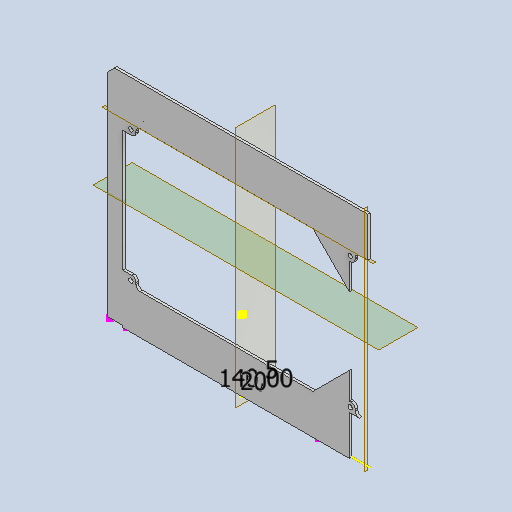
# Autodesk Inventor part: sensor board
Saved by Autodesk Inventor 2025 (Build 290162000, 162)
## iProperties
Created: 2026-07-27
Part Number: sensor board
Material: Типовые
Document SubType Name: Modeling
Designer: garin
Density: 1 g/cm^3
Appearance: По умолчанию
Author: garin
Autodesk Inventor part; units mm, degrees
ref_plane "YZ Plane" through (0, 0, 0) normal (1, 0, 0) x (0, 1, 0)
ref_plane "XZ Plane" through (0, 0, 0) normal (0, 1, 0) x (-1, 0, 0)
ref_plane "XY Plane" through (0, 0, 0) normal (0, 0, 1) x (1, 0, 0)
sketch "Эскиз1" plane through (0, 0, 0) normal (0, 0, 1) x (1, 0, 0)
  line L0 (0, 0) -> (-80.25, 0) construction
  line L1 (-80.25, 0) -> (-80.25, -18.086) construction
  line L2 (-80.25, -18.086) -> (0, -18.086) construction
  line L3 (0, -18.086) -> (0, 0) construction
  line L4 (-80.25, -18.086) -> (-80.25, -42.186) construction
  line L5 (-80.25, -18.086) -> (-56.15, -18.086) construction
  line L6 (-80.25, -42.186) -> (76.75, -42.186)
  line L7 (76.75, -42.186) -> (76.75, 91.214)
  line L8 (76.75, 91.214) -> (-80.25, 91.214)
  line L9 (-80.25, 91.214) -> (-80.25, -42.186)
  line L10 (-80.25, -42.186) -> (76.75, -42.186)
  line L11 (76.75, -42.186) -> (76.75, -18.086)
  line L12 (76.75, -18.086) -> (-60.75, -18.086)
  line L13 (-80.25, -18.086) -> (-80.25, -42.186)
  line L14 (76.75, 91.214) -> (-80.25, 91.214)
  line L15 (-80.25, 91.214) -> (-80.25, 67.114)
  line L16 (-80.25, 67.114) -> (76.75, 67.114)
  line L17 (76.75, 67.114) -> (76.75, 91.214)
  line L18 (-80.25, -42.186) -> (-71.25, -42.186)
  line L19 (-71.25, -42.186) -> (-71.25, 88.814)
  line L20 (-71.25, 88.814) -> (-80.25, 88.814)
  line L21 (-80.25, 88.814) -> (-80.25, -42.186)
  line L22 (76.75, -42.186) -> (65.75, -42.186)
  line L23 (65.75, -42.186) -> (65.75, 88.814)
  line L24 (65.75, 88.814) -> (76.75, 88.814)
  line L25 (76.75, 88.814) -> (76.75, -42.186)
  line L26 (76.75, -42.186) -> (41.75, -42.186)
  line L27 (41.75, -42.186) -> (61.75, -42.186) construction
  line L28 (76.75, 23.314) -> (-80.25, 23.314) construction
  line L29 (65.75, 67.114) -> (65.75, 45.114)
  line L30 (65.75, 45.114) -> (43.75, 67.114)
  line L31 (65.75, 45.114) -> (96.8627, 45.114) construction
  line L32 (-71.25, 23.314) -> (-80.25, 23.314)
  line L33 (-80.25, 23.314) -> (-80.25, 50.814)
  line L34 (-80.25, 50.814) -> (-71.25, 50.814)
  line L35 (-71.25, 50.814) -> (-71.25, 23.314)
  line L36 (0, -18.086) -> (0, 67.114) construction
  line L37 (-80.25, 23.314) -> (76.75, 23.314) construction
  line L38 (76.75, 91.214) -> (76.75, -42.186)
  line L39 (76.75, 24.514) -> (-71.25, 24.514) construction
  line L40 (65.75, 3.914) -> (43.75, -18.086)
  line L41 (60.8932, -21.756) -> (60.8932, -22.256) construction
  line L42 (60.8932, -21.756) -> (61.2932, -21.756) construction
  line L43 (61.2932, -21.756) -> (61.2932, -22.256) construction
  line L44 (61.2932, -22.256) -> (60.8932, -22.256) construction
  line L45 (61.2932, -26.836) -> (61.2932, -27.336) construction
  line L46 (61.2932, -27.336) -> (60.8932, -27.336) construction
  line L47 (60.8932, -26.836) -> (60.8932, -27.336) construction
  line L48 (60.8932, -26.836) -> (61.2932, -26.836) construction
  line L49 (60.8932, -31.916) -> (60.8932, -32.416) construction
  line L50 (60.8932, -31.916) -> (61.2932, -31.916) construction
  line L51 (61.2932, -31.916) -> (61.2932, -32.416) construction
  line L52 (61.2932, -32.416) -> (60.8932, -32.416) construction
  line L53 (-64.3932, -21.756) -> (-64.3932, -22.256) construction
  line L54 (-64.7932, -22.256) -> (-64.3932, -22.256) construction
  line L55 (-64.7932, -21.756) -> (-64.7932, -22.256) construction
  line L56 (-64.3932, -21.756) -> (-64.7932, -21.756) construction
  line L57 (-64.7932, -26.836) -> (-64.7932, -27.336) construction
  line L58 (-64.3932, -26.836) -> (-64.7932, -26.836) construction
  line L59 (-64.3932, -26.836) -> (-64.3932, -27.336) construction
  line L60 (-64.7932, -27.336) -> (-64.3932, -27.336) construction
  line L61 (-64.3932, -31.916) -> (-64.3932, -32.416) construction
  line L62 (-64.7932, -32.416) -> (-64.3932, -32.416) construction
  line L63 (-64.7932, -31.916) -> (-64.7932, -32.416) construction
  line L64 (-64.3932, -31.916) -> (-64.7932, -31.916) construction
  line L65 (-64.3932, 80.944) -> (-64.3932, 81.444) construction
  line L66 (-64.3932, 80.944) -> (-64.7932, 80.944) construction
  line L67 (-64.7932, 80.944) -> (-64.7932, 81.444) construction
  line L68 (-64.7932, 81.444) -> (-64.3932, 81.444) construction
  line L69 (-64.7932, 75.864) -> (-64.7932, 76.364) construction
  line L70 (-64.7932, 76.364) -> (-64.3932, 76.364) construction
  line L71 (-64.3932, 75.864) -> (-64.3932, 76.364) construction
  line L72 (-64.3932, 75.864) -> (-64.7932, 75.864) construction
  line L73 (-64.3932, 70.784) -> (-64.3932, 71.284) construction
  line L74 (-64.3932, 70.784) -> (-64.7932, 70.784) construction
  line L75 (-64.7932, 70.784) -> (-64.7932, 71.284) construction
  line L76 (-64.7932, 71.284) -> (-64.3932, 71.284) construction
  line L77 (60.8932, 80.944) -> (60.8932, 81.444) construction
  line L78 (61.2932, 81.444) -> (60.8932, 81.444) construction
  line L79 (61.2932, 80.944) -> (61.2932, 81.444) construction
  line L80 (60.8932, 80.944) -> (61.2932, 80.944) construction
  line L81 (61.2932, 75.864) -> (61.2932, 76.364) construction
  line L82 (60.8932, 75.864) -> (61.2932, 75.864) construction
  line L83 (60.8932, 75.864) -> (60.8932, 76.364) construction
  line L84 (61.2932, 76.364) -> (60.8932, 76.364) construction
  line L85 (60.8932, 70.784) -> (60.8932, 71.284) construction
  line L86 (61.2932, 71.284) -> (60.8932, 71.284) construction
  line L87 (61.2932, 70.784) -> (61.2932, 71.284) construction
  line L88 (60.8932, 70.784) -> (61.2932, 70.784) construction
  line L89 (-8.01, 84.194) -> (-8.01, 83.754) construction
  line L90 (-8.45, 84.194) -> (-8.01, 84.194) construction
  line L91 (-8.45, 83.754) -> (-8.45, 84.194) construction
  line L92 (-8.01, 83.754) -> (-8.45, 83.754) construction
  line L93 (-5.47, 84.194) -> (-5.47, 83.754) construction
  line L94 (-5.91, 84.194) -> (-5.47, 84.194) construction
  line L95 (-5.91, 83.754) -> (-5.91, 84.194) construction
  line L96 (-5.47, 83.754) -> (-5.91, 83.754) construction
  line L97 (-2.93, 84.194) -> (-2.93, 83.754) construction
  line L98 (-3.37, 84.194) -> (-2.93, 84.194) construction
  line L99 (-3.37, 83.754) -> (-3.37, 84.194) construction
  line L100 (-2.93, 83.754) -> (-3.37, 83.754) construction
  line L101 (-0.39, 84.194) -> (-0.39, 83.754) construction
  line L102 (-0.83, 84.194) -> (-0.39, 84.194) construction
  line L103 (-0.83, 83.754) -> (-0.83, 84.194) construction
  line L104 (-0.39, 83.754) -> (-0.83, 83.754) construction
  line L105 (2.15, 84.194) -> (2.15, 83.754) construction
  line L106 (1.71, 84.194) -> (2.15, 84.194) construction
  line L107 (1.71, 83.754) -> (1.71, 84.194) construction
  line L108 (2.15, 83.754) -> (1.71, 83.754) construction
  line L109 (4.69, 84.194) -> (4.69, 83.754) construction
  line L110 (4.25, 84.194) -> (4.69, 84.194) construction
  line L111 (4.25, 83.754) -> (4.25, 84.194) construction
  line L112 (4.69, 83.754) -> (4.25, 83.754) construction
  line L113 (66.3002, 49.1566) -> (65.9891, 48.8455) construction
  line L114 (65.9891, 49.4678) -> (66.3002, 49.1566) construction
  line L115 (65.6779, 49.1566) -> (65.9891, 49.4678) construction
  line L116 (65.9891, 48.8455) -> (65.6779, 49.1566) construction
  line L117 (64.5041, 50.9527) -> (64.193, 50.6416) construction
  line L118 (64.193, 51.2638) -> (64.5041, 50.9527) construction
  line L119 (63.8819, 50.9527) -> (64.193, 51.2638) construction
  line L120 (64.193, 50.6416) -> (63.8819, 50.9527) construction
  line L121 (62.7081, 52.7487) -> (62.397, 52.4376) construction
  line L122 (62.397, 53.0599) -> (62.7081, 52.7487) construction
  line L123 (62.0858, 52.7487) -> (62.397, 53.0599) construction
  line L124 (62.397, 52.4376) -> (62.0858, 52.7487) construction
  line L125 (60.912, 54.5448) -> (60.6009, 54.2337) construction
  line L126 (60.6009, 54.8559) -> (60.912, 54.5448) construction
  line L127 (60.2898, 54.5448) -> (60.6009, 54.8559) construction
  line L128 (60.6009, 54.2337) -> (60.2898, 54.5448) construction
  line L129 (59.116, 56.3409) -> (58.8048, 56.0297) construction
  line L130 (58.8048, 56.652) -> (59.116, 56.3409) construction
  line L131 (58.4937, 56.3409) -> (58.8048, 56.652) construction
  line L132 (58.8048, 56.0297) -> (58.4937, 56.3409) construction
  line L133 (57.3199, 58.1369) -> (57.0088, 57.8258) construction
  line L134 (57.0088, 58.448) -> (57.3199, 58.1369) construction
  line L135 (56.6977, 58.1369) -> (57.0088, 58.448) construction
  line L136 (57.0088, 57.8258) -> (56.6977, 58.1369) construction
  line L137 (57.3199, -9.1089) -> (57.0088, -8.7978) construction
  line L138 (57.0088, -8.7978) -> (56.6977, -9.1089) construction
  line L139 (56.6977, -9.1089) -> (57.0088, -9.42) construction
  line L140 (57.0088, -9.42) -> (57.3199, -9.1089) construction
  line L141 (59.116, -7.3129) -> (58.8048, -7.0017) construction
  line L142 (58.8048, -7.0017) -> (58.4937, -7.3129) construction
  line L143 (58.4937, -7.3129) -> (58.8048, -7.624) construction
  line L144 (58.8048, -7.624) -> (59.116, -7.3129) construction
  line L145 (60.912, -5.5168) -> (60.6009, -5.2057) construction
  line L146 (60.6009, -5.2057) -> (60.2898, -5.5168) construction
  line L147 (60.2898, -5.5168) -> (60.6009, -5.8279) construction
  line L148 (60.6009, -5.8279) -> (60.912, -5.5168) construction
  line L149 (62.7081, -3.7207) -> (62.397, -3.4096) construction
  line L150 (62.397, -3.4096) -> (62.0858, -3.7207) construction
  line L151 (62.0858, -3.7207) -> (62.397, -4.0319) construction
  line L152 (62.397, -4.0319) -> (62.7081, -3.7207) construction
  line L153 (64.5041, -1.9247) -> (64.193, -1.6136) construction
  line L154 (64.193, -1.6136) -> (63.8819, -1.9247) construction
  line L155 (63.8819, -1.9247) -> (64.193, -2.2358) construction
  line L156 (64.193, -2.2358) -> (64.5041, -1.9247) construction
  line L157 (66.3002, -0.1286) -> (65.9891, 0.1825) construction
  line L158 (65.9891, 0.1825) -> (65.6779, -0.1286) construction
  line L159 (65.6779, -0.1286) -> (65.9891, -0.4398) construction
  line L160 (65.9891, -0.4398) -> (66.3002, -0.1286) construction
  line L161 (69.73, 30.774) -> (69.29, 30.774) construction
  line L162 (69.73, 31.214) -> (69.73, 30.774) construction
  line L163 (69.29, 31.214) -> (69.73, 31.214) construction
  line L164 (69.29, 30.774) -> (69.29, 31.214) construction
  line L165 (69.73, 28.234) -> (69.29, 28.234) construction
  line L166 (69.73, 28.674) -> (69.73, 28.234) construction
  line L167 (69.29, 28.674) -> (69.73, 28.674) construction
  line L168 (69.29, 28.234) -> (69.29, 28.674) construction
  line L169 (69.73, 25.694) -> (69.29, 25.694) construction
  line L170 (69.73, 26.134) -> (69.73, 25.694) construction
  line L171 (69.29, 26.134) -> (69.73, 26.134) construction
  line L172 (69.29, 25.694) -> (69.29, 26.134) construction
  line L173 (69.73, 23.154) -> (69.29, 23.154) construction
  line L174 (69.73, 23.594) -> (69.73, 23.154) construction
  line L175 (69.29, 23.594) -> (69.73, 23.594) construction
  line L176 (69.29, 23.154) -> (69.29, 23.594) construction
  line L177 (69.73, 20.614) -> (69.29, 20.614) construction
  line L178 (69.73, 21.054) -> (69.73, 20.614) construction
  line L179 (69.29, 21.054) -> (69.73, 21.054) construction
  line L180 (69.29, 20.614) -> (69.29, 21.054) construction
  line L181 (69.73, 18.074) -> (69.29, 18.074) construction
  line L182 (69.73, 18.514) -> (69.73, 18.074) construction
  line L183 (69.29, 18.514) -> (69.73, 18.514) construction
  line L184 (69.29, 18.074) -> (69.29, 18.514) construction
  line L185 (-73.23, 52.304) -> (-72.79, 52.304) construction
  line L186 (-73.23, 51.864) -> (-73.23, 52.304) construction
  line L187 (-72.79, 51.864) -> (-73.23, 51.864) construction
  line L188 (-72.79, 52.304) -> (-72.79, 51.864) construction
  line L189 (-73.23, 54.844) -> (-72.79, 54.844) construction
  line L190 (-73.23, 54.404) -> (-73.23, 54.844) construction
  line L191 (-72.79, 54.404) -> (-73.23, 54.404) construction
  line L192 (-72.79, 54.844) -> (-72.79, 54.404) construction
  line L193 (-73.23, 57.384) -> (-72.79, 57.384) construction
  line L194 (-73.23, 56.944) -> (-73.23, 57.384) construction
  line L195 (-72.79, 56.944) -> (-73.23, 56.944) construction
  line L196 (-72.79, 57.384) -> (-72.79, 56.944) construction
  line L197 (-73.23, 59.924) -> (-72.79, 59.924) construction
  line L198 (-73.23, 59.484) -> (-73.23, 59.924) construction
  line L199 (-72.79, 59.484) -> (-73.23, 59.484) construction
  line L200 (-72.79, 59.924) -> (-72.79, 59.484) construction
  line L201 (-73.23, 62.464) -> (-72.79, 62.464) construction
  line L202 (-73.23, 62.024) -> (-73.23, 62.464) construction
  line L203 (-72.79, 62.024) -> (-73.23, 62.024) construction
  line L204 (-72.79, 62.464) -> (-72.79, 62.024) construction
  line L205 (-73.23, 65.004) -> (-72.79, 65.004) construction
  line L206 (-73.23, 64.564) -> (-73.23, 65.004) construction
  line L207 (-72.79, 64.564) -> (-73.23, 64.564) construction
  line L208 (-72.79, 65.004) -> (-72.79, 64.564) construction
  line L209 (-8.4415, -35.51) -> (-8.4415, -35.07) construction
  line L210 (-8.4415, -35.07) -> (-8.8815, -35.07) construction
  line L211 (-8.8815, -35.07) -> (-8.8815, -35.51) construction
  line L212 (-8.8815, -35.51) -> (-8.4415, -35.51) construction
  line L213 (-5.9015, -35.51) -> (-5.9015, -35.07) construction
  line L214 (-5.9015, -35.07) -> (-6.3415, -35.07) construction
  line L215 (-6.3415, -35.07) -> (-6.3415, -35.51) construction
  line L216 (-6.3415, -35.51) -> (-5.9015, -35.51) construction
  line L217 (-3.3615, -35.51) -> (-3.3615, -35.07) construction
  line L218 (-3.3615, -35.07) -> (-3.8015, -35.07) construction
  line L219 (-3.8015, -35.07) -> (-3.8015, -35.51) construction
  line L220 (-3.8015, -35.51) -> (-3.3615, -35.51) construction
  line L221 (-0.8215, -35.51) -> (-0.8215, -35.07) construction
  line L222 (-0.8215, -35.07) -> (-1.2615, -35.07) construction
  line L223 (-1.2615, -35.07) -> (-1.2615, -35.51) construction
  line L224 (-1.2615, -35.51) -> (-0.8215, -35.51) construction
  line L225 (1.7185, -35.51) -> (1.7185, -35.07) construction
  line L226 (1.7185, -35.07) -> (1.2785, -35.07) construction
  line L227 (1.2785, -35.07) -> (1.2785, -35.51) construction
  line L228 (1.2785, -35.51) -> (1.7185, -35.51) construction
  line L229 (4.2585, -35.51) -> (4.2585, -35.07) construction
  line L230 (4.2585, -35.07) -> (3.8185, -35.07) construction
  line L231 (3.8185, -35.07) -> (3.8185, -35.51) construction
  line L232 (3.8185, -35.51) -> (4.2585, -35.51) construction
  line L233 (4.0385, -35.07) -> (4.0385, -35.51) construction
  line L234 (3.8185, -35.29) -> (4.2585, -35.29) construction
  circle A0 centre (4.0385, -35.29) radius 1
  line L235 (60.8932, -32.166) -> (61.2932, -32.166) construction
  line L236 (61.0932, -31.916) -> (61.0932, -32.416) construction
  circle A1 centre (61.0932, -32.166) radius 1
  line L237 (56.8532, -8.9533) -> (57.1644, -9.2645) construction
  line L238 (57.1644, -8.9533) -> (56.8532, -9.2645) construction
  circle A2 centre (57.0088, -9.1089) radius 1
  line L239 (69.29, 18.294) -> (69.73, 18.294) construction
  line L240 (69.51, 18.514) -> (69.51, 18.074) construction
  circle A3 centre (69.51, 18.294) radius 1
  line L241 (56.8532, 57.9813) -> (57.1644, 58.2925) construction
  line L242 (57.1644, 57.9813) -> (56.8532, 58.2925) construction
  circle A4 centre (57.0088, 58.1369) radius 1
  line L243 (61.2932, 81.194) -> (60.8932, 81.194) construction
  line L244 (61.0932, 80.944) -> (61.0932, 81.444) construction
  circle A5 centre (61.0932, 81.194) radius 1
  line L245 (4.69, 83.974) -> (4.25, 83.974) construction
  line L246 (4.47, 83.754) -> (4.47, 84.194) construction
  circle A6 centre (4.47, 83.974) radius 1
  line L247 (-64.3932, 81.194) -> (-64.7932, 81.194) construction
  line L248 (-64.5932, 80.944) -> (-64.5932, 81.444) construction
  circle A7 centre (-64.5932, 81.194) radius 1
  line L249 (-73.01, 64.564) -> (-73.01, 65.004) construction
  line L250 (-72.79, 64.784) -> (-73.23, 64.784) construction
  circle A8 centre (-73.01, 64.784) radius 1
  line L251 (-64.3932, -32.166) -> (-64.7932, -32.166) construction
  line L252 (-64.5932, -32.416) -> (-64.5932, -31.916) construction
  circle A9 centre (-64.5932, -32.166) radius 1
  line L253 (-58.9618, 72.1218) -> (-58.9618, 71.9362) projected
  line L254 (-58.9618, 71.9362) -> (-58.7762, 71.9362) projected
  line L255 (-58.7762, 71.9362) -> (-58.7762, 72.1218) projected
  line L256 (-58.7762, 72.1218) -> (-58.9618, 72.1218) projected
  line L257 (-58.869, 72.1218) -> (-58.869, 71.9362) construction
  line L258 (-58.9618, 72.029) -> (-58.7762, 72.029) construction
  circle A10 centre (-58.869, 72.029) radius 1
  line L259 (-80.25, -42.186) -> (-34.25, -42.186)
  line L260 (-34.25, -42.186) -> (-34.25, -18.086)
  line L261 (-34.25, -18.086) -> (-80.25, -18.086)
  line L262 (-80.25, -18.086) -> (-80.25, -42.186)
  line L263 (-80.25, 67.114) -> (-34.25, 67.114)
  line L264 (-34.25, 67.114) -> (-34.25, 91.214)
  line L265 (-34.25, 91.214) -> (-80.25, 91.214)
  line L266 (-80.25, 91.214) -> (-80.25, 67.114)
  line L267 (76.75, -42.186) -> (30.75, -42.186)
  line L268 (30.75, -42.186) -> (30.75, -18.086)
  line L269 (30.75, -18.086) -> (76.75, -18.086)
  line L270 (76.75, -18.086) -> (76.75, -42.186)
  line L271 (76.75, 91.214) -> (30.75, 91.214)
  line L272 (30.75, 91.214) -> (30.75, 67.114)
  line L273 (30.75, 67.114) -> (76.75, 67.114)
  line L274 (76.75, 67.114) -> (76.75, 91.214)
  line L275 (76.75, -42.186) -> (-80.25, -42.186)
  line L276 (-80.25, -42.186) -> (-80.25, -40.986)
  line L277 (-80.25, -40.986) -> (76.75, -40.986)
  line L278 (76.75, -40.986) -> (76.75, -42.186)
  line L279 (76.75, 91.214) -> (-80.25, 91.214)
  line L280 (-80.25, 91.214) -> (-80.25, 90.014)
  line L281 (-80.25, 90.014) -> (76.75, 90.014)
  line L282 (76.75, 90.014) -> (76.75, 91.214)
  line L283 (-80.25, 88.814) -> (-34.25, 88.814)
  line L284 (-34.25, 88.814) -> (-34.25, 86.814)
  line L285 (-34.25, 86.814) -> (-80.25, 86.814)
  line L286 (-80.25, 86.814) -> (-80.25, 88.814)
  line L287 (-34.25, 86.814) -> (-45.25, 86.814) construction
  line L288 (-45.25, 86.814) -> (-56.25, 86.814) construction
  line L289 (-56.25, 86.814) -> (-67.25, 86.814) construction
  line L290 (-67.25, 86.814) -> (-80.25, 86.814) construction
  circle A11 centre (-45.25, 86.814) radius 1
  circle A12 centre (-56.25, 86.814) radius 1
  circle A13 centre (-67.25, 86.814) radius 1
  circle A14 centre (-45.25, -37.786) radius 1
  circle A15 centre (-56.25, -37.786) radius 1
  circle A16 centre (-67.25, -37.786) radius 1
  circle A17 centre (45.25, 86.814) radius 1
  circle A18 centre (56.25, 86.814) radius 1
  circle A19 centre (67.25, 86.814) radius 1
  circle A20 centre (45.25, -37.786) radius 1
  circle A21 centre (56.25, -37.786) radius 1
  circle A22 centre (67.25, -37.786) radius 1
  line L291 (-80.25, -42.186) -> (-66.25, -42.186) construction
  line L292 (-66.25, -42.186) -> (-66.25, -15.086) construction
  line L293 (-66.25, -15.086) -> (-80.25, -15.086) construction
  line L294 (-80.25, -15.086) -> (-80.25, -42.186) construction
  circle A23 centre (-66.25, -15.086) radius 1.35
  line L295 (-66.75, -12.086) -> (-65.75, -12.086)
  line L296 (-63.25, -14.586) -> (-63.25, -15.586)
  line L297 (-63.25, -18.086) -> (-69.25, -18.086) construction
  line L298 (-69.25, -15.586) -> (-69.25, -14.586)
  line L299 (-69.25, -12.086) -> (-63.25, -18.086) construction
  line L300 (-63.25, -12.086) -> (-69.25, -18.086) construction
  arc A24 (-66.75, -12.086) -> (-69.25, -14.586) centre (-66.75, -14.586) ccw
  line L301 (-71.75, -18.086) -> (-80.25, -18.086)
  line L302 (-63.25, -18.086) -> (76.75, -18.086) construction
  arc A25 (-71.75, -18.086) -> (-69.25, -15.586) centre (-71.75, -15.586) ccw
  arc A26 (-63.25, -15.586) -> (-60.75, -18.086) centre (-60.75, -15.586) ccw
  arc A27 (-63.25, -14.586) -> (-65.75, -12.086) centre (-65.75, -14.586) ccw
  circle A28 centre (-66.25, 64.114) radius 1.35
  line L303 (-66.75, 61.114) -> (-65.75, 61.114)
  line L304 (-63.25, 63.614) -> (-63.25, 64.614)
  line L305 (-69.25, 64.614) -> (-69.25, 63.614)
  arc A29 (-69.25, 63.614) -> (-66.75, 61.114) centre (-66.75, 63.614) ccw
  arc A30 (-69.25, 64.614) -> (-71.75, 67.114) centre (-71.75, 64.614) ccw
  arc A31 (-60.75, 67.114) -> (-63.25, 64.614) centre (-60.75, 64.614) ccw
  arc A32 (-65.75, 61.114) -> (-63.25, 63.614) centre (-65.75, 63.614) ccw
  circle A33 centre (66.25, -15.086) radius 1.35
  line L306 (66.75, -12.086) -> (65.75, -12.086)
  line L307 (63.25, -14.586) -> (63.25, -15.586)
  line L308 (69.25, -15.586) -> (69.25, -14.586)
  arc A34 (69.25, -14.586) -> (66.75, -12.086) centre (66.75, -14.586) ccw
  arc A35 (69.25, -15.586) -> (71.75, -18.086) centre (71.75, -15.586) ccw
  arc A36 (60.75, -18.086) -> (63.25, -15.586) centre (60.75, -15.586) ccw
  arc A37 (65.75, -12.086) -> (63.25, -14.586) centre (65.75, -14.586) ccw
  line L309 (69.25, 64.614) -> (69.25, 63.614)
  arc A38 (71.75, 67.114) -> (69.25, 64.614) centre (71.75, 64.614) ccw
  arc A39 (66.75, 61.114) -> (69.25, 63.614) centre (66.75, 63.614) ccw
  line L310 (66.75, 61.114) -> (65.75, 61.114)
  arc A40 (63.25, 63.614) -> (65.75, 61.114) centre (65.75, 63.614) ccw
  circle A41 centre (66.25, 64.114) radius 1.35
  arc A42 (63.25, 64.614) -> (60.75, 67.114) centre (60.75, 64.614) ccw
  line L311 (63.25, 63.614) -> (63.25, 64.614)
  line L312 (-66.75, 61.114) -> (-71.25, 61.114)
  line L313 (-66.75, -12.086) -> (-80.25, -12.086)
  line L314 (-80.25, -12.086) -> (-80.25, -18.086)
  line L315 (-80.25, 91.214) -> (-70.25, 91.214)
  line L316 (-70.25, 91.214) -> (-70.25, 81.214)
  line L317 (-70.25, 81.214) -> (-80.25, 81.214)
  line L318 (-80.25, 81.214) -> (-80.25, 91.214)
  point P0 (-71.25, -18.086)
  point P1 (-71.25, 67.114)
  point P2 (71.75, 70.413)
  point P3 (65.75, -18.086)
  point P4 (-71.25, 50.814)
  point P5 (-80.25, -18.086)
  point P6 (76.75, -18.086)
  point P7 (76.75, -18.086)
  point P8 (-71.25, -18.0355)
  point P9 (-71.25, -18.086)
  point P10 (76.75, -18.086)
  point P11 (-34.25, 90.014)
  point P12 (-71.25, -40.986)
  point P13 (-71.25, 67.0635)
  point P14 (-70.25, 88.814)
  point P15 (-71.25, 86.814)
  point P16 (-71.25, -12.086)
  dimension "d0" = 80.25
  dimension "d1" = 18.086
  dimension "d2" = 24.1
  dimension "d3" = 90
  dimension "d4" = 157
  dimension "d5" = 133.4
  dimension "d6" = 157
  dimension "d7" = 24.1
  dimension "d8" = 157
  dimension "d9" = 24.1
  dimension "d10" = 9
  dimension "d11" = 131
  dimension "d12" = 11
  dimension "d13" = 131
  dimension "d16" = 35
  dimension "d19" = 22
  dimension "d20" = 135
  dimension "d21" = 27.5
  dimension "d34" = 2
  dimension "d35" = 2
  dimension "d36" = 2
  dimension "d37" = 2
  dimension "d38" = 2
  dimension "d39" = 2
  dimension "d40" = 2
  dimension "d41" = 2
  dimension "d42" = 2
  dimension "d43" = 2
  dimension "d44" = 2
  dimension "d45" = 46
  dimension "d46" = 24.1
  dimension "d47" = 46
  dimension "d48" = 46
  dimension "d49" = 46
  dimension "d50" = 1.2
  dimension "d51" = 1.2
  dimension "d52" = 2
  dimension "d53" = 11
  dimension "d54" = 11
  dimension "d55" = 11
  dimension "d56" = 2
  dimension "d57" = 2
  dimension "d58" = 2
  dimension "d59" = 14
  dimension "d60" = 27.1
  dimension "d61" = 2.7
  dimension "d62" = 6
  dimension "d63" = 6
  dimension "d64" = 2.5
  dimension "d65" = 2.5
  dimension "d66" = 2.5
  dimension "d67" = 10
  dimension "d68" = 10
  constraints: 246 end point, 61 midpoint, 50 symmetric about line, 43 centre point, 34 parallel, 32 point on circle, 29 point on line, 21 perpendicular, 20 horizontal, 8 tangent, 4 coincident, 2 equal length, 1 collinear, 1 equal radius, 1 vertical, 24 other
  measures "d0" distance of L2.end L1.end
  measures "d1" distance of L1.end L0.end
  measures "d2" distance of L1.end L4.end
  measures "d3" angle of L4 L5
  measures "d4" distance of L8.end L7.end
  measures "d5" distance of L7.end L6.end
  measures "d6" distance of L13.start L11.end
  measures "d7" distance of L11.end L10.end
  measures "d8" distance of L16.end L15.end
  measures "d9" distance of L15.end L14.end
  measures "d10" distance of L20.end L19.end
  measures "d11" distance of L19.end L18.end
  measures "d12" distance of L23.end L24.end
  measures "d13" distance of L22.end L23.end
  measures "d16" distance of L10.end L26.end
  measures "d19" distance of L29.start L29.end
  measures "d20" angle of L31 L30
  measures "d21" distance of L32.end L33.end
  measures "d34" diameter of A0
  measures "d35" diameter of A1
  measures "d36" diameter of A2
  measures "d37" diameter of A3
  measures "d38" diameter of A4
  measures "d39" diameter of A5
  measures "d40" diameter of A6
  measures "d41" diameter of A7
  measures "d42" diameter of A8
  measures "d43" diameter of A9
  measures "d44" diameter of A10
  measures "d45" distance of L261.end L260.end
  measures "d46" distance of L260.end L259.end
  measures "d47" distance of L265.end L264.end
  measures "d48" distance of L268.end L269.end
  measures "d49" distance of L273.end L272.end
  measures "d50" distance of L275.end L276.end
  measures "d51" distance of L280.end L279.end
  measures "d52" distance of L283.end L284.end
  measures "d53" distance of L284.end L287.end
  measures "d54" distance of L287.end L288.end
  measures "d55" distance of L288.end L289.end
  measures "d56" diameter of A11
  measures "d57" diameter of A12
  measures "d58" diameter of A13
  measures "d59" distance of L293.end L292.end
  measures "d60" distance of L292.end L291.end
  measures "d61" diameter of A23
  measures "d62" distance of L297.start L297.end
  measures "d63" distance of L300.start L297.start
  measures "d64" radius of A24
  measures "d65" radius of A25
  measures "d66" radius of A27
  measures "d67" distance of L316.end L317.end
  measures "d68" distance of L315.end L316.end
extrude "Выдавливание1" add sketch "Эскиз1" along normal blind 1.5 contours L19 L277 L260 L6 | L9 L261 L19 L277 | L260 L277 L268 L6 | L19 L261 L12 L260 L277 | L9 L313 L19 A25 L261 | L268 L277 L23 L6 | L260 L12 L268 L277 | L261 A25 L19 | L19 A25 L298 A24 L295 A27 L296 A26 L261 | L9 L32 L19 L313 | L268 L12 L23 L277 | L19 L313 A24 L298 A25 | L9 L34 L19 L32 | L9 L16 A30 L19 L34 | L40 L23 A37 L307 A36 L12 | L23 A33 L306 A34 L308 A35 L12 | L12 A36 L307 A37 L23 A33 | L9 L317 L19 L16 | L9 L285 L19 L317 | L16 L19 A30 | L19 A30 L305 A29 L312 | L30 L16 A42 L311 A40 L23 | L16 L23 L24 L7 | L9 L20 L19 L285 | L317 L316 L285 A13 A12 A11 L264 L16 L19 | L19 L285 L316 L317 | L16 A31 L304 A32 L303 A29 L305 A30 L19 | A40 L311 A42 L16 L23 A41 | L23 A41 L16 A38 L309 A39 L310 | L16 L272 L281 L7 L24 L23 | L9 L281 L316 L283 L20 | L19 L283 L316 L285 | L16 L264 L281 L272 | L281 L272 L8 L7 | L9 L8 L316 L281 | L316 L283 L264 L285 A11 A12 A13 | L281 L264 L8 L272 | L316 L8 L264 L281 | L281 L264 L283 L316 | A13 L285 | L285 A13 | A11 L285 | L285 A11 | A12 L285 | L285 A12 | A0 | A1 | A2 | A4 | A5 | A6 | A7 | A8 | A9 | A10 | A14 | A15 | A16 | A17 | A18 | A19 | A20 | A21
sketch "Эскиз2" plane through (-80.25, -42.186, 0) normal (0, -1, 0) x (1, 0, 0)
  line L0 (124, 0) -> (146, 0) projected
  line L1 (157, 0) -> (0, 0) projected
  line L2 (0, 0) -> (157, 0)
  line L3 (157, 0) -> (78.5, 0)
  line L4 (78.5, 0) -> (78.5, -20)
  line L5 (78.5, -20) -> (73.5, -20)
  line L6 (73.5, -20) -> (49.6649, 0)
  line L7 (78.5, -20) -> (83.5, -20)
  line L8 (83.5, -20) -> (107.3351, 0)
  point P0 (80.25, 0)
  point P1 (126.4, 0)
  point P2 (10, 0)
  dimension "d22" = 20
  dimension "d24" = 5
  dimension "d25" = 140
  constraints: 14 end point, 2 symmetric about line, 1 collinear, 1 horizontal, 1 midpoint, 1 perpendicular, 1 point on line
  measures "d22" distance of L3.end L4.end
  measures "d24" distance of L4.end L5.end
  measures "d25" angle of L5 L6
chamfer "Фаска1" distance 4 angle 45 1 edges at (-80.25, 91.214, 0.75)
chamfer "Фаска2" [suppressed]
ref_plane "РабПлоскость1" through (-76.25, 24.514, 0) normal (0, -1, 0) x (1, 0, 0)
ref_plane "РабПлоскость2" through (-1.75, -38.186, 0) normal (1, 0, 0) x (0, 0, -1)
ref_plane "РабПлоскость3" through (75.15, -38.186, 0) normal (1, 0, 0) x (0, 0, -1)
ref_plane "РабПлоскость4" through (-76.25, 67.114, 0) normal (0, 1, 0) x (1, 0, 0)
sketch "Эскиз3" plane through (0, 0, 1.5) normal (0, 0, 1) x (1, 0, 0)
  point P0 (0, 0)
sketch "Эскиз4" plane through (0, 0, 0) normal (0, 0, -1) x (-1, 0, 0)
  point P0 (0, 0)
chamfer "Фаска3" [suppressed]
